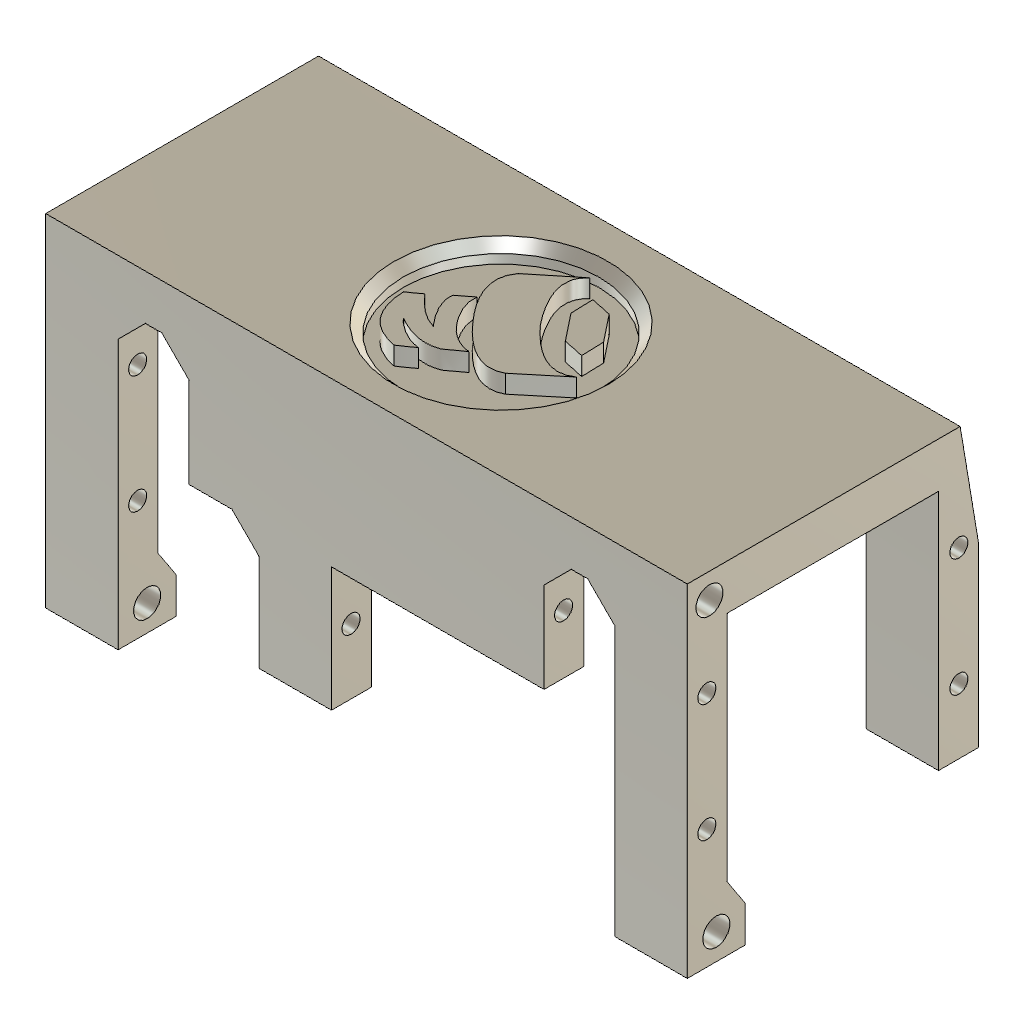
Servo Block native (Autodesk Fusion 360 design; units mm, degrees)
part number: 2026-10-13-22-38-25-267
Autodesk Fusion 360 part; units mm, degrees
(part 1 of 2)
ref_plane "WorkPlane1" through (37.5, 0, 0) normal (1, 0, 0) x (0, 1, 0)
sketch "Plate" plane through (37.5, 0, 0) normal (1, 0, 0) x (0, 0, -1)
  line L0 (-60.7428, -21.1733) -> (-60.7428, 10.9267)
  line L1 (-60.7428, 10.9267) -> (-65.7428, 10.9267)
  line L2 (-65.7428, 10.9267) -> (-65.7428, -21.1733)
  line L3 (-65.7428, -21.1733) -> (-60.7428, -21.1733)
  dimension "d74" = 60.7428
  dimension "d75" = 21.1733
  dimension "d76" = 10.9267
  dimension "d77" = 65.7428
  constraint vertical L0
  constraint horizontal L1
  constraint vertical L2
  constraint horizontal L3
  measures "d74" horizontal distance of origin L0.start
  measures "d75" vertical distance of origin L0.start
  measures "d76" vertical distance of origin L0.end
  measures "d77" horizontal distance of origin L1.end
extrude "Plate (1)" add sketch "Plate" along normal mid plane 70.7696
ref_plane "WorkPlane2" through (0, -18.9733, 0) normal (0, 1, 0) x (0, 0, 1)
sketch "Back wall" plane through (0, -18.9733, 0) normal (0, 1, 0) x (1, 0, 0)
  line L0 (2.1152, -65.7428) -> (2.1152, -28.0592)
  line L1 (2.1152, -28.0592) -> (10.1152, -28.0592)
  line L2 (10.1152, -28.0592) -> (10.1152, -57.7428)
  line L3 (10.1152, -57.7428) -> (13.1152, -60.7428)
  line L4 (13.1152, -60.7428) -> (14.9152, -60.7428)
  line L5 (14.9152, -60.7428) -> (17.9152, -57.7428)
  line L6 (17.9152, -57.7428) -> (17.9152, -47.7592)
  line L7 (17.9152, -47.7592) -> (22.6508, -47.7592)
  line L8 (22.6508, -47.7592) -> (25.6508, -44.7592)
  line L9 (25.6508, -44.7592) -> (25.6508, -34.0592)
  line L10 (25.6508, -34.0592) -> (33.6508, -34.0592)
  line L11 (33.6508, -34.0592) -> (33.6508, -47.7592)
  line L12 (33.6508, -47.7592) -> (57.0848, -47.7592)
  line L13 (57.0848, -47.7592) -> (57.0848, -57.7428)
  line L14 (57.0848, -57.7428) -> (60.0848, -60.7428)
  line L15 (60.0848, -60.7428) -> (61.8848, -60.7428)
  line L16 (61.8848, -60.7428) -> (64.8848, -57.7428)
  line L17 (64.8848, -57.7428) -> (64.8848, -28.0592)
  line L18 (64.8848, -28.0592) -> (72.8848, -28.0592)
  line L19 (72.8848, -28.0592) -> (72.8848, -65.7428)
  line L20 (72.8848, -65.7428) -> (2.1152, -65.7428)
  dimension "d78" = 2.1152
  dimension "d79" = 65.7428
  dimension "d80" = 28.0592
  dimension "d81" = 10.1152
  dimension "d82" = 57.7428
  dimension "d83" = 13.1152
  dimension "d84" = 60.7428
  dimension "d85" = 14.9152
  dimension "d86" = 17.9152
  dimension "d87" = 57.7428
  dimension "d88" = 47.7592
  dimension "d89" = 22.6508
  dimension "d90" = 25.6508
  dimension "d91" = 44.7592
  dimension "d92" = 34.0592
  dimension "d93" = 33.6508
  dimension "d94" = 47.7592
  dimension "d95" = 57.0848
  dimension "d96" = 57.7428
  dimension "d97" = 60.0848
  dimension "d98" = 60.7428
  dimension "d99" = 61.8848
  dimension "d100" = 64.8848
  dimension "d101" = 57.7428
  dimension "d102" = 28.0592
  dimension "d103" = 72.8848
  constraint vertical L0
  constraint horizontal L1
  constraint vertical L2
  constraint horizontal L4
  constraint vertical L6
  constraint horizontal L7
  constraint vertical L9
  constraint horizontal L10
  constraint vertical L11
  constraint horizontal L12
  constraint vertical L13
  constraint horizontal L15
  constraint vertical L17
  constraint horizontal L18
  constraint vertical L19
  constraint horizontal L20
  measures "d78" horizontal distance of origin L0.start
  measures "d79" vertical distance of origin L0.start
  measures "d80" vertical distance of origin L0.end
  measures "d81" horizontal distance of origin L1.end
  measures "d82" vertical distance of origin L2.end
  measures "d83" horizontal distance of origin L3.end
  measures "d84" vertical distance of origin L3.end
  measures "d85" horizontal distance of origin L4.end
  measures "d86" horizontal distance of origin L5.end
  measures "d87" vertical distance of origin L5.end
  measures "d88" vertical distance of origin L6.end
  measures "d89" horizontal distance of origin L7.end
  measures "d90" horizontal distance of origin L8.end
  measures "d91" vertical distance of origin L8.end
  measures "d92" vertical distance of origin L9.end
  measures "d93" horizontal distance of origin L10.end
  measures "d94" vertical distance of origin L11.end
  measures "d95" horizontal distance of origin L12.end
  measures "d96" vertical distance of origin L13.end
  measures "d97" horizontal distance of origin L14.end
  measures "d98" vertical distance of origin L14.end
  measures "d99" horizontal distance of origin L15.end
  measures "d100" horizontal distance of origin L16.end
  measures "d101" vertical distance of origin L16.end
  measures "d102" vertical distance of origin L17.end
  measures "d103" horizontal distance of origin L18.end
extrude "Back wall (1)" add sketch "Back wall" along normal mid plane 4.4
ref_plane "WorkPlane3" through (0, 8.7267, 0) normal (0, 1, 0) x (0, 0, 1)
sketch "Front wall" plane through (0, 8.7267, 0) normal (0, 1, 0) x (1, 0, 0)
  line L0 (2.1152, -65.7428) -> (2.1152, -34.0592)
  line L1 (2.1152, -34.0592) -> (10.1152, -34.0592)
  line L2 (10.1152, -34.0592) -> (10.1152, -57.7428)
  line L3 (10.1152, -57.7428) -> (13.1152, -60.7428)
  line L4 (13.1152, -60.7428) -> (14.9152, -60.7428)
  line L5 (14.9152, -60.7428) -> (17.9152, -57.7428)
  line L6 (17.9152, -57.7428) -> (17.9152, -47.7592)
  line L7 (17.9152, -47.7592) -> (22.6508, -47.7592)
  line L8 (22.6508, -47.7592) -> (25.6508, -44.7592)
  line L9 (25.6508, -44.7592) -> (25.6508, -34.0592)
  line L10 (25.6508, -34.0592) -> (33.6508, -34.0592)
  line L11 (33.6508, -34.0592) -> (33.6508, -57.7428)
  line L12 (33.6508, -57.7428) -> (57.0848, -57.7428)
  line L13 (57.0848, -57.7428) -> (60.0848, -60.7428)
  line L14 (60.0848, -60.7428) -> (61.8848, -60.7428)
  line L15 (61.8848, -60.7428) -> (64.8848, -57.7428)
  line L16 (64.8848, -57.7428) -> (64.8848, -34.0592)
  line L17 (64.8848, -34.0592) -> (72.8848, -34.0592)
  line L18 (72.8848, -34.0592) -> (72.8848, -65.7428)
  line L19 (72.8848, -65.7428) -> (2.1152, -65.7428)
  dimension "d104" = 2.1152
  dimension "d105" = 65.7428
  dimension "d106" = 34.0592
  dimension "d107" = 10.1152
  dimension "d108" = 57.7428
  dimension "d109" = 13.1152
  dimension "d110" = 60.7428
  dimension "d111" = 14.9152
  dimension "d112" = 17.9152
  dimension "d113" = 57.7428
  dimension "d114" = 47.7592
  dimension "d115" = 22.6508
  dimension "d116" = 25.6508
  dimension "d117" = 44.7592
  dimension "d118" = 34.0592
  dimension "d119" = 33.6508
  dimension "d120" = 57.7428
  dimension "d121" = 57.0848
  dimension "d122" = 60.0848
  dimension "d123" = 60.7428
  dimension "d124" = 61.8848
  dimension "d125" = 64.8848
  dimension "d126" = 57.7428
  dimension "d127" = 34.0592
  dimension "d128" = 72.8848
  constraint vertical L0
  constraint horizontal L1
  constraint vertical L2
  constraint horizontal L4
  constraint vertical L6
  constraint horizontal L7
  constraint vertical L9
  constraint horizontal L10
  constraint vertical L11
  constraint horizontal L12
  constraint horizontal L14
  constraint vertical L16
  constraint horizontal L17
  constraint vertical L18
  constraint horizontal L19
  measures "d104" horizontal distance of origin L0.start
  measures "d105" vertical distance of origin L0.start
  measures "d106" vertical distance of origin L0.end
  measures "d107" horizontal distance of origin L1.end
  measures "d108" vertical distance of origin L2.end
  measures "d109" horizontal distance of origin L3.end
  measures "d110" vertical distance of origin L3.end
  measures "d111" horizontal distance of origin L4.end
  measures "d112" horizontal distance of origin L5.end
  measures "d113" vertical distance of origin L5.end
  measures "d114" vertical distance of origin L6.end
  measures "d115" horizontal distance of origin L7.end
  measures "d116" horizontal distance of origin L8.end
  measures "d117" vertical distance of origin L8.end
  measures "d118" vertical distance of origin L9.end
  measures "d119" horizontal distance of origin L10.end
  measures "d120" vertical distance of origin L11.end
  measures "d121" horizontal distance of origin L12.end
  measures "d122" horizontal distance of origin L13.end
  measures "d123" vertical distance of origin L13.end
  measures "d124" horizontal distance of origin L14.end
  measures "d125" horizontal distance of origin L15.end
  measures "d126" vertical distance of origin L15.end
  measures "d127" vertical distance of origin L16.end
  measures "d128" horizontal distance of origin L17.end
extrude "Front wall (1)" add sketch "Front wall" along normal mid plane 4.4
ref_plane "WorkPlane4" through (37.5, 0, 0) normal (1, 0, 0) x (0, 1, 0)
sketch "Front rake" plane through (37.5, 0, 0) normal (1, 0, 0) x (0, 0, -1)
  line L0 (-65.7428, 8.9267) -> (-53.7428, 10.9267)
  line L1 (-53.7428, 10.9267) -> (-53.7428, 11.4267)
  line L2 (-53.7428, 11.4267) -> (-66.2428, 11.4267)
  line L3 (-66.2428, 11.4267) -> (-66.2428, 8.9267)
  line L4 (-66.2428, 8.9267) -> (-65.7428, 8.9267)
  dimension "d129" = 65.7428
  dimension "d130" = 8.9267
  dimension "d131" = 53.7428
  dimension "d132" = 10.9267
  dimension "d133" = 11.4267
  dimension "d134" = 66.2428
  constraint vertical L1
  constraint horizontal L2
  constraint vertical L3
  constraint horizontal L4
  measures "d129" horizontal distance of origin L0.start
  measures "d130" vertical distance of origin L0.start
  measures "d131" horizontal distance of origin L0.end
  measures "d132" vertical distance of origin L0.end
  measures "d133" vertical distance of origin L1.end
  measures "d134" horizontal distance of origin L2.end
extrude "Front rake (1)" cut sketch "Front rake" along normal mid plane 72.7696
ref_plane "WorkPlane5" through (6.1152, 0, 0) normal (1, 0, 0) x (0, 1, 0)
sketch "Foot L" plane through (6.1152, 0, 0) normal (1, 0, 0) x (0, 0, -1)
  line L0 (-28.0592, -17.2733) -> (-28.0592, -14.7733)
  line L1 (-28.0592, -14.7733) -> (-32.0592, -14.7733)
  line L2 (-32.0592, -14.7733) -> (-35.1038, -16.7733)
  line L3 (-35.1038, -16.7733) -> (-35.1038, -17.2733)
  line L4 (-35.1038, -17.2733) -> (-28.0592, -17.2733)
  dimension "d135" = 28.0592
  dimension "d136" = 17.2733
  dimension "d137" = 14.7733
  dimension "d138" = 32.0592
  dimension "d139" = 35.1038
  dimension "d140" = 16.7733
  constraint vertical L0
  constraint horizontal L1
  constraint vertical L3
  constraint horizontal L4
  measures "d135" horizontal distance of origin L0.start
  measures "d136" vertical distance of origin L0.start
  measures "d137" vertical distance of origin L0.end
  measures "d138" horizontal distance of origin L1.end
  measures "d139" horizontal distance of origin L2.end
  measures "d140" vertical distance of origin L2.end
extrude "Foot L (1)" add sketch "Foot L" along normal mid plane 8
ref_plane "WorkPlane6" through (68.8848, 0, 0) normal (1, 0, 0) x (0, 1, 0)
sketch "Foot R" plane through (68.8848, 0, 0) normal (1, 0, 0) x (0, 0, -1)
  line L0 (-28.0592, -17.2733) -> (-28.0592, -14.7733)
  line L1 (-28.0592, -14.7733) -> (-32.0592, -14.7733)
  line L2 (-32.0592, -14.7733) -> (-35.1038, -16.7733)
  line L3 (-35.1038, -16.7733) -> (-35.1038, -17.2733)
  line L4 (-35.1038, -17.2733) -> (-28.0592, -17.2733)
  dimension "d141" = 28.0592
  dimension "d142" = 17.2733
  dimension "d143" = 14.7733
  dimension "d144" = 32.0592
  dimension "d145" = 35.1038
  dimension "d146" = 16.7733
  constraint vertical L0
  constraint horizontal L1
  constraint vertical L3
  constraint horizontal L4
  measures "d141" horizontal distance of origin L0.start
  measures "d142" vertical distance of origin L0.start
  measures "d143" vertical distance of origin L0.end
  measures "d144" horizontal distance of origin L1.end
  measures "d145" horizontal distance of origin L2.end
  measures "d146" vertical distance of origin L2.end
extrude "Foot R (1)" add sketch "Foot R" along normal mid plane 8
ref_plane "WorkPlane7" through (37.5, 0, 0) normal (1, 0, 0) x (0, 1, 0)
sketch "Rod hole back low" plane through (37.5, 0, 0) normal (1, 0, 0) x (0, 0, -1)
  circle A0 centre (-41.2428, -19.0233) radius 1
  dimension "d147" = 2
  dimension "d148" = 41.2428
  dimension "d149" = 19.0233
  measures "d147" diameter of A0
  measures "d148" horizontal distance of origin A0.centre
  measures "d149" vertical distance of origin A0.centre
extrude "Rod hole back low (1)" cut sketch "Rod hole back low" along normal mid plane 71.7696
ref_plane "WorkPlane8" through (37.5, 0, 0) normal (1, 0, 0) x (0, 1, 0)
sketch "Rod hole back high" plane through (37.5, 0, 0) normal (1, 0, 0) x (0, 0, -1)
  circle A0 centre (-54.2428, -19.0233) radius 1
  dimension "d150" = 2
  dimension "d151" = 54.2428
  dimension "d152" = 19.0233
  measures "d150" diameter of A0
  measures "d151" horizontal distance of origin A0.centre
  measures "d152" vertical distance of origin A0.centre
extrude "Rod hole back high (1)" cut sketch "Rod hole back high" along normal mid plane 71.7696
ref_plane "WorkPlane9" through (37.5, 0, 0) normal (1, 0, 0) x (0, 1, 0)
sketch "Rod hole front low" plane through (37.5, 0, 0) normal (1, 0, 0) x (0, 0, -1)
  circle A0 centre (-41.2428, 8.7767) radius 1
  dimension "d153" = 2
  dimension "d154" = 41.2428
  dimension "d155" = 8.7767
  measures "d153" diameter of A0
  measures "d154" horizontal distance of origin A0.centre
  measures "d155" vertical distance of origin A0.centre
extrude "Rod hole front low (1)" cut sketch "Rod hole front low" along normal mid plane 71.7696
ref_plane "WorkPlane10" through (37.5, 0, 0) normal (1, 0, 0) x (0, 1, 0)
sketch "Rod hole front high" plane through (37.5, 0, 0) normal (1, 0, 0) x (0, 0, -1)
  circle A0 centre (-54.2428, 8.7767) radius 1
  dimension "d156" = 2
  dimension "d157" = 54.2428
  dimension "d158" = 8.7767
  measures "d156" diameter of A0
  measures "d157" horizontal distance of origin A0.centre
  measures "d158" vertical distance of origin A0.centre
extrude "Rod hole front high (1)" cut sketch "Rod hole front high" along normal mid plane 71.7696
ref_plane "WorkPlane11" through (6.8652, 0, 0) normal (1, 0, 0) x (0, 1, 0)
sketch "Screw hole top L" plane through (6.8652, 0, 0) normal (1, 0, 0) x (0, 0, -1)
  circle A0 centre (-62.9667, -18.7303) radius 1.5
  dimension "d159" = 3
  dimension "d160" = 62.9667
  dimension "d161" = 18.7303
  measures "d159" diameter of A0
  measures "d160" horizontal distance of origin A0.centre
  measures "d161" vertical distance of origin A0.centre
extrude "Screw hole top L (1)" cut sketch "Screw hole top L" along normal mid plane 10.5
ref_plane "WorkPlane12" through (68.1348, 0, 0) normal (1, 0, 0) x (0, 1, 0)
sketch "Screw hole top R" plane through (68.1348, 0, 0) normal (1, 0, 0) x (0, 0, -1)
  circle A0 centre (-62.9667, -18.7303) radius 1.5
  dimension "d162" = 3
  dimension "d163" = 62.9667
  dimension "d164" = 18.7303
  measures "d162" diameter of A0
  measures "d163" horizontal distance of origin A0.centre
  measures "d164" vertical distance of origin A0.centre
extrude "Screw hole top R (1)" cut sketch "Screw hole top R" along normal mid plane 10.5
ref_plane "WorkPlane13" through (6.1152, 0, 0) normal (1, 0, 0) x (0, 1, 0)
sketch "Screw hole foot L" plane through (6.1152, 0, 0) normal (1, 0, 0) x (0, 0, -1)
  circle A0 centre (-30.943, -17.9733) radius 1.5
  dimension "d165" = 3
  dimension "d166" = 30.943
  dimension "d167" = 17.9733
  measures "d165" diameter of A0
  measures "d166" horizontal distance of origin A0.centre
  measures "d167" vertical distance of origin A0.centre
extrude "Screw hole foot L (1)" cut sketch "Screw hole foot L" along normal mid plane 9
ref_plane "WorkPlane14" through (68.8848, 0, 0) normal (1, 0, 0) x (0, 1, 0)
sketch "Screw hole foot R" plane through (68.8848, 0, 0) normal (1, 0, 0) x (0, 0, -1)
  circle A0 centre (-30.943, -17.9733) radius 1.5
  dimension "d168" = 3
  dimension "d169" = 30.943
  dimension "d170" = 17.9733
  measures "d168" diameter of A0
  measures "d169" horizontal distance of origin A0.centre
  measures "d170" vertical distance of origin A0.centre
extrude "Screw hole foot R (1)" cut sketch "Screw hole foot R" along normal mid plane 9
ref_plane "WorkPlane15" through (0, 0, 64.9928) normal (0, 0, 1) x (1, 0, 0)
sketch "Logo recess" plane through (0, 0, 64.9928) normal (0, 0, 1) x (1, 0, 0)
  circle A0 centre (37.6833, -6.5179) radius 10.7908
  dimension "d171" = 21.5816
  dimension "d172" = 37.6833
  dimension "d173" = 6.5179
  measures "d171" diameter of A0
  measures "d172" horizontal distance of origin A0.centre
  measures "d173" vertical distance of origin A0.centre
extrude "Logo recess (1)" cut sketch "Logo recess" along normal mid plane 2.5
chamfer "Logo rim chamfer" distance 1 angle 45 1 edges at (27.6227, -2.6158, 65.7428) tangent chain off
ref_plane "WorkPlane16" through (0, 0, 64.4928) normal (0, 0, 1) x (1, 0, 0)
sketch "Logo 1" plane through (0, 0, 64.4928) normal (0, 0, 1) x (1, 0, 0)
  line L0 (32.3923, -6.5174) -> (33.8802, -5.3582)
  spline S0 degree 5 poles (33.8802, -5.3582) (33.879, -5.3659) (33.8766, -5.3815) (33.8732, -5.4048) (33.869, -5.4359) (33.8645, -5.4751) (33.8606, -5.5143) (33.8573, -5.5538) (33.8546, -5.5933) (33.8526, -5.6331) (33.8511, -5.6729) (33.8503, -5.7129) (33.8501, -5.753) (33.8504, -5.7933) (33.8514, -5.8336) (33.853, -5.8741) (33.8551, -5.9146) (33.8579, -5.9553) (33.8612, -5.9961) (33.8652, -6.037) (33.8697, -6.078) (33.8748, -6.1191) (33.8804, -6.1603) (33.8866, -6.2016) (33.8934, -6.243) (33.9008, -6.2844) (33.9086, -6.3259) (33.9171, -6.3675) (33.9261, -6.4091) (33.9356, -6.4509) (33.9457, -6.4927) (33.9562, -6.5345) (33.9673, -6.5765) (33.9789, -6.6185) (33.9911, -6.6606) (34.0037, -6.7027) (34.0168, -6.7449) (34.0305, -6.7871) (34.0446, -6.8294) (34.0593, -6.8717) (34.0744, -6.914) (34.09, -6.9564) (34.106, -6.9989) (34.1225, -7.0414) (34.1395, -7.084) (34.1569, -7.1266) (34.1748, -7.1692) (34.1932, -7.2119) (34.212, -7.2546) (34.2313, -7.2973) (34.2509, -7.3401) (34.2711, -7.3829) (34.2916, -7.4257) (34.3125, -7.4686) (34.3339, -7.5115) (34.3557, -7.5544) (34.3779, -7.5974) (34.4006, -7.6405) (34.4236, -7.6836) (34.4471, -7.7266) (34.4709, -7.7697) (34.4951, -7.8127) (34.5197, -7.8558) (34.5446, -7.8988) (34.5699, -7.9419) (34.5956, -7.985) (34.6218, -8.0283) (34.6485, -8.0718) (34.6756, -8.1153) (34.703, -8.1588) (34.7307, -8.2023) (34.7586, -8.2455) (34.7867, -8.2886) (34.815, -8.3314) (34.8435, -8.3741) (34.8725, -8.417) (34.9021, -8.4602) (34.9325, -8.5041) (34.9636, -8.5486) (34.9955, -8.5936) (35.0277, -8.6387) (35.06, -8.6834) (35.0918, -8.7271) (35.1228, -8.7692) (35.1526, -8.8094) (35.1813, -8.8475) (35.2089, -8.8839) (35.2359, -8.919) (35.2626, -8.9533) (35.2895, -8.9874) (35.3168, -9.0217) (35.3445, -9.0561) (35.3726, -9.0907) (35.4009, -9.1252) (35.4293, -9.1594) (35.4577, -9.193) (35.4859, -9.2262) (35.5141, -9.2588) (35.5422, -9.291) (35.5704, -9.3228) (35.5986, -9.3544) (35.627, -9.3857) (35.6556, -9.4169) (35.6844, -9.4478) (35.7132, -9.4785) (35.7422, -9.5088) (35.7711, -9.5388) (35.7998, -9.5683) (35.8284, -9.5973) (35.8569, -9.6258) (35.8854, -9.6539) (35.9141, -9.6819) (35.9432, -9.7098) (35.9729, -9.7379) (36.0031, -9.7659) (36.0332, -9.7936) (36.0628, -9.8205) (36.0914, -9.8463) (36.1187, -9.8707) (36.1453, -9.8943) (36.1723, -9.9177) (36.201, -9.9423) (36.233, -9.9689) (36.269, -9.9985) (36.3094, -10.031) (36.3536, -10.066) (36.4005, -10.1025) (36.4488, -10.1395) (36.4973, -10.1759) (36.545, -10.2108) (36.5913, -10.2439) (36.6362, -10.275) (36.6802, -10.3045) (36.7235, -10.3328) (36.7669, -10.3604) (36.8107, -10.3877) (36.855, -10.4147) (36.8998, -10.4415) (36.945, -10.4679) (36.9902, -10.4937) (37.0353, -10.5187) (37.0801, -10.5429) (37.1245, -10.5661) (37.1686, -10.5885) (37.2125, -10.6101) (37.2563, -10.631) (37.3, -10.6513) (37.3437, -10.671) (37.3873, -10.6901) (37.4308, -10.7086) (37.4741, -10.7265) (37.5171, -10.7437) (37.5599, -10.7603) (37.6025, -10.7761) (37.6447, -10.7914) (37.6867, -10.806) (37.7284, -10.82) (37.7699, -10.8335) (37.8111, -10.8464) (37.8519, -10.8587) (37.8925, -10.8705) (37.9327, -10.8817) (37.9725, -10.8924) (38.0119, -10.9025) (38.0509, -10.9122) (38.0894, -10.9213) (38.1275, -10.93) (38.1652, -10.9382) (38.2023, -10.946) (38.239, -10.9533) (38.2751, -10.9603) (38.3106, -10.9668) (38.3456, -10.973) (38.3799, -10.9788) (38.4136, -10.9842) (38.4466, -10.9894) (38.4789, -10.9943) (38.5105, -10.999) (38.5412, -11.0034) (38.5711, -11.0077) (38.6001, -11.0119) (38.6225, -11.0151) (38.639, -11.0174) (38.6498, -11.0189) (38.6551, -11.0197) knots 0 0 0 0 0 0 0.00555556 0.01111111 0.01666667 0.02222222 0.02777778 0.03333333 0.03888889 0.04444444 0.05 0.05555556 0.06111111 0.06666667 0.07222222 0.07777778 0.08333333 0.08888889 0.09444444 0.1 0.10555556 0.11111111 0.11666667 0.12222222 0.12777778 0.13333333 0.13888889 0.14444444 0.15 0.15555556 0.16111111 0.16666667 0.17222222 0.17777778 0.18333333 0.18888889 0.19444444 0.2 0.20555556 0.21111111 0.21666667 0.22222222 0.22777778 0.23333333 0.23888889 0.24444444 0.25 0.25555556 0.26111111 0.26666667 0.27222222 0.27777778 0.28333333 0.28888889 0.29444444 0.3 0.30555556 0.31111111 0.31666667 0.32222222 0.32777778 0.33333333 0.33888889 0.34444444 0.35 0.35555556 0.36111111 0.36666667 0.37222222 0.37777778 0.38333333 0.38888889 0.39444444 0.4 0.40555556 0.41111111 0.41666667 0.42222222 0.42777778 0.43333333 0.43888889 0.44444444 0.45 0.45555556 0.46111111 0.46666667 0.47222222 0.47777778 0.48333333 0.48888889 0.49444444 0.5 0.50555556 0.51111111 0.51666667 0.52222222 0.52777778 0.53333333 0.53888889 0.54444444 0.55 0.55555556 0.56111111 0.56666667 0.57222222 0.57777778 0.58333333 0.58888889 0.59444444 0.6 0.60555556 0.61111111 0.61666667 0.62222222 0.62777778 0.63333333 0.63888889 0.64444444 0.65 0.65555556 0.66111111 0.66666667 0.67222222 0.67777778 0.68333333 0.68888889 0.69444444 0.7 0.70555556 0.71111111 0.71666667 0.72222222 0.72777778 0.73333333 0.73888889 0.74444444 0.75 0.75555556 0.76111111 0.76666667 0.77222222 0.77777778 0.78333333 0.78888889 0.79444444 0.8 0.80555556 0.81111111 0.81666667 0.82222222 0.82777778 0.83333333 0.83888889 0.84444444 0.85 0.85555556 0.86111111 0.86666667 0.87222222 0.87777778 0.88333333 0.88888889 0.89444444 0.9 0.90555556 0.91111111 0.91666667 0.92222222 0.92777778 0.93333333 0.93888889 0.94444444 0.95 0.95555556 0.96111111 0.96666667 0.97222222 0.97777778 0.98333333 0.98888889 0.99444444 1 1 1 1 1 1
  spline S1 degree 5 poles (38.6551, -11.0197) (38.6411, -11.0298) (38.613, -11.05) (38.5707, -11.0807) (38.5138, -11.1222) (38.4421, -11.1751) (38.3696, -11.2289) (38.2966, -11.2835) (38.2231, -11.3386) (38.1494, -11.3939) (38.0757, -11.4489) (38.0023, -11.5031) (37.9293, -11.5563) (37.8568, -11.6084) (37.7846, -11.6595) (37.7125, -11.7104) (37.6397, -11.7622) (37.5656, -11.816) (37.4898, -11.8727) (37.4122, -11.9325) (37.333, -11.9949) (37.2531, -12.0583) (37.174, -12.12) (37.0972, -12.1773) (37.0241, -12.2277) (36.9556, -12.2695) (36.8918, -12.3021) (36.832, -12.3267) (36.7746, -12.3459) (36.7179, -12.3623) (36.6604, -12.3785) (36.6012, -12.3959) (36.5404, -12.4146) (36.4784, -12.4337) (36.4159, -12.4523) (36.3534, -12.4692) (36.2912, -12.4842) (36.2293, -12.4973) (36.1673, -12.5089) (36.1051, -12.5196) (36.0424, -12.5296) (35.9793, -12.5391) (35.9156, -12.5478) (35.8517, -12.5557) (35.7876, -12.5625) (35.7234, -12.5681) (35.6591, -12.5726) (35.5946, -12.576) (35.5299, -12.5784) (35.465, -12.5798) (35.3999, -12.5804) (35.3345, -12.58) (35.2689, -12.5788) (35.2031, -12.5765) (35.1372, -12.5734) (35.0712, -12.5692) (35.005, -12.5641) (34.9386, -12.558) (34.8721, -12.551) (34.8055, -12.5431) (34.7387, -12.5342) (34.6718, -12.5245) (34.6047, -12.5138) (34.5375, -12.5023) (34.4703, -12.4899) (34.4029, -12.4767) (34.3353, -12.4625) (34.2677, -12.4475) (34.2, -12.4316) (34.1322, -12.4148) (34.0642, -12.3972) (33.9962, -12.3788) (33.9281, -12.3595) (33.8599, -12.3394) (33.7916, -12.3185) (33.7233, -12.2968) (33.6549, -12.2743) (33.5864, -12.251) (33.5178, -12.2269) (33.4492, -12.202) (33.3805, -12.1764) (33.3117, -12.15) (33.2429, -12.1228) (33.174, -12.0948) (33.1051, -12.0662) (33.0361, -12.0367) (32.9671, -12.0066) (32.898, -11.9758) (32.8289, -11.9442) (32.7597, -11.9119) (32.6904, -11.8789) (32.6212, -11.8452) (32.5518, -11.8109) (32.4825, -11.7758) (32.4131, -11.7401) (32.3436, -11.7037) (32.2742, -11.6666) (32.2047, -11.6289) (32.1351, -11.5905) (32.0655, -11.5515) (31.9959, -11.5118) (31.9402, -11.4796) (31.8984, -11.4551) (31.8705, -11.4387) (31.8566, -11.4304) knots 0 0 0 0 0 0 0.01 0.02 0.03 0.04 0.05 0.06 0.07 0.08 0.09 0.1 0.11 0.12 0.13 0.14 0.15 0.16 0.17 0.18 0.19 0.2 0.21 0.22 0.23 0.24 0.25 0.26 0.27 0.28 0.29 0.3 0.31 0.32 0.33 0.34 0.35 0.36 0.37 0.38 0.39 0.4 0.41 0.42 0.43 0.44 0.45 0.46 0.47 0.48 0.49 0.5 0.51 0.52 0.53 0.54 0.55 0.56 0.57 0.58 0.59 0.6 0.61 0.62 0.63 0.64 0.65 0.66 0.67 0.68 0.69 0.7 0.71 0.72 0.73 0.74 0.75 0.76 0.77 0.78 0.79 0.8 0.81 0.82 0.83 0.84 0.85 0.86 0.87 0.88 0.89 0.9 0.91 0.92 0.93 0.94 0.95 0.96 0.97 0.98 0.99 1 1 1 1 1 1
  spline S2 degree 5 poles (31.8566, -11.4304) (31.8588, -11.4336) (31.8632, -11.4398) (31.8694, -11.4488) (31.877, -11.4598) (31.8858, -11.4722) (31.8941, -11.4839) (31.903, -11.4958) (31.9139, -11.5098) (31.928, -11.5272) (31.9463, -11.5489) (31.9685, -11.5748) (31.9939, -11.6036) (32.0212, -11.634) (32.0495, -11.6646) (32.078, -11.6944) (32.1065, -11.7234) (32.1354, -11.7519) (32.1651, -11.7805) (32.1959, -11.8097) (32.2279, -11.8396) (32.2611, -11.8702) (32.2954, -11.9012) (32.3305, -11.9326) (32.3663, -11.9639) (32.4025, -11.9951) (32.4394, -12.0262) (32.4769, -12.0573) (32.515, -12.0884) (32.5538, -12.1196) (32.5933, -12.151) (32.6335, -12.1824) (32.6743, -12.2139) (32.7158, -12.2453) (32.7577, -12.2767) (32.8002, -12.3079) (32.8431, -12.3391) (32.8866, -12.3701) (32.9306, -12.4009) (32.975, -12.4317) (33.02, -12.4623) (33.0655, -12.4927) (33.1114, -12.523) (33.1577, -12.5531) (33.2045, -12.5829) (33.2517, -12.6125) (33.2993, -12.6418) (33.3473, -12.6709) (33.3957, -12.6996) (33.4445, -12.7281) (33.4937, -12.7562) (33.5432, -12.7841) (33.593, -12.8116) (33.6433, -12.8387) (33.6938, -12.8655) (33.7447, -12.8918) (33.7959, -12.9177) (33.8474, -12.9432) (33.8992, -12.9683) (33.9513, -12.9928) (34.0037, -13.0169) (34.0563, -13.0405) (34.1092, -13.0635) (34.1623, -13.086) (34.2157, -13.108) (34.2694, -13.1294) (34.3232, -13.1502) (34.3773, -13.1704) (34.4316, -13.19) (34.4861, -13.209) (34.5407, -13.2273) (34.5956, -13.2448) (34.6506, -13.2617) (34.7058, -13.2778) (34.7612, -13.2932) (34.8167, -13.3078) (34.8723, -13.3216) (34.928, -13.3347) (34.9839, -13.3469) (35.0398, -13.3582) (35.0959, -13.3687) (35.1519, -13.3782) (35.2081, -13.3868) (35.2642, -13.3944) (35.3204, -13.4011) (35.3767, -13.4068) (35.4217, -13.4105) (35.4554, -13.4129) (35.4779, -13.4143) (35.4892, -13.4149) knots 0 0 0 0 0 0 0.01176471 0.02352941 0.03529412 0.04705882 0.05882353 0.07058824 0.08235294 0.09411765 0.10588235 0.11764706 0.12941176 0.14117647 0.15294118 0.16470588 0.17647059 0.18823529 0.2 0.21176471 0.22352941 0.23529412 0.24705882 0.25882353 0.27058824 0.28235294 0.29411765 0.30588235 0.31764706 0.32941176 0.34117647 0.35294118 0.36470588 0.37647059 0.38823529 0.4 0.41176471 0.42352941 0.43529412 0.44705882 0.45882353 0.47058824 0.48235294 0.49411765 0.50588235 0.51764706 0.52941176 0.54117647 0.55294118 0.56470588 0.57647059 0.58823529 0.6 0.61176471 0.62352941 0.63529412 0.64705882 0.65882353 0.67058824 0.68235294 0.69411765 0.70588235 0.71764706 0.72941176 0.74117647 0.75294118 0.76470588 0.77647059 0.78823529 0.8 0.81176471 0.82352941 0.83529412 0.84705882 0.85882353 0.87058824 0.88235294 0.89411765 0.90588235 0.91764706 0.92941176 0.94117647 0.95294118 0.96470588 0.97647059 0.98823529 1 1 1 1 1 1
  spline S3 degree 5 poles (35.4892, -13.4149) (35.4804, -13.4214) (35.4629, -13.4343) (35.4366, -13.4537) (35.4017, -13.4793) (35.3583, -13.5112) (35.315, -13.5429) (35.2719, -13.5744) (35.2291, -13.6056) (35.1864, -13.6366) (35.1438, -13.6675) (35.1015, -13.6981) (35.0594, -13.7285) (35.0175, -13.7587) (34.9757, -13.7886) (34.9342, -13.8184) (34.8929, -13.8479) (34.8517, -13.8772) (34.8108, -13.9063) (34.7701, -13.9352) (34.7296, -13.9638) (34.6893, -13.9922) (34.6491, -14.0204) (34.6092, -14.0484) (34.5695, -14.0762) (34.5299, -14.1037) (34.4906, -14.131) (34.4515, -14.1581) (34.4126, -14.1849) (34.3739, -14.2115) (34.3354, -14.2378) (34.2972, -14.2639) (34.2592, -14.2898) (34.2213, -14.3154) (34.1837, -14.3408) (34.1464, -14.366) (34.1092, -14.3909) (34.0722, -14.4156) (34.0355, -14.44) (33.999, -14.4642) (33.9627, -14.4882) (33.9338, -14.5071) (33.9123, -14.5212) (33.898, -14.5305) (33.8908, -14.5352) knots 0 0 0 0 0 0 0.025 0.05 0.075 0.1 0.125 0.15 0.175 0.2 0.225 0.25 0.275 0.3 0.325 0.35 0.375 0.4 0.425 0.45 0.475 0.5 0.525 0.55 0.575 0.6 0.625 0.65 0.675 0.7 0.725 0.75 0.775 0.8 0.825 0.85 0.875 0.9 0.925 0.95 0.975 1 1 1 1 1 1
  spline S4 degree 5 poles (33.8908, -14.5352) (33.8804, -14.5332) (33.8595, -14.5291) (33.8283, -14.5229) (33.7868, -14.5144) (33.7351, -14.5035) (33.6837, -14.4924) (33.6324, -14.4809) (33.5814, -14.4691) (33.5306, -14.457) (33.48, -14.4446) (33.4296, -14.4319) (33.3794, -14.4189) (33.3295, -14.4056) (33.2797, -14.392) (33.2302, -14.378) (33.181, -14.3637) (33.1319, -14.3492) (33.0831, -14.3342) (33.0346, -14.319) (32.9863, -14.3034) (32.9382, -14.2875) (32.8903, -14.2713) (32.8427, -14.2548) (32.7954, -14.238) (32.7482, -14.2208) (32.7014, -14.2034) (32.6547, -14.1856) (32.6084, -14.1674) (32.5622, -14.1489) (32.5164, -14.1301) (32.4708, -14.1109) (32.4254, -14.0914) (32.3804, -14.0716) (32.3356, -14.0514) (32.2911, -14.0309) (32.2468, -14.0101) (32.2028, -13.9889) (32.1591, -13.9674) (32.1157, -13.9455) (32.0726, -13.9233) (32.0297, -13.9008) (31.9871, -13.8779) (31.9448, -13.8547) (31.9028, -13.8311) (31.8611, -13.8072) (31.8197, -13.783) (31.7786, -13.7584) (31.7378, -13.7334) (31.6972, -13.7081) (31.657, -13.6825) (31.6171, -13.6565) (31.5775, -13.6302) (31.5382, -13.6035) (31.4993, -13.5765) (31.4606, -13.5492) (31.4222, -13.5215) (31.3842, -13.4934) (31.3465, -13.465) (31.3091, -13.4363) (31.2721, -13.4072) (31.2353, -13.3778) (31.1989, -13.348) (31.1629, -13.3179) (31.1271, -13.2875) (31.0917, -13.2567) (31.0567, -13.2256) (31.0219, -13.1941) (30.9876, -13.1623) (30.9535, -13.1301) (30.9198, -13.0977) (30.8865, -13.0649) (30.8535, -13.0317) (30.8208, -12.9982) (30.7885, -12.9644) (30.7565, -12.9303) (30.7249, -12.8958) (30.6936, -12.861) (30.6627, -12.8259) (30.6322, -12.7905) (30.602, -12.7547) (30.5722, -12.7187) (30.5427, -12.6823) (30.5136, -12.6455) (30.4848, -12.6085) (30.4564, -12.5711) (30.4284, -12.5335) (30.4008, -12.4955) (30.3735, -12.4572) (30.3465, -12.4186) (30.32, -12.3798) (30.2937, -12.3406) (30.2679, -12.3011) (30.2424, -12.2613) (30.2173, -12.2212) (30.1925, -12.1808) (30.1681, -12.1402) (30.1441, -12.0992) (30.1205, -12.058) (30.0972, -12.0164) (30.0743, -11.9746) (30.0517, -11.9325) (30.0295, -11.8902) (30.0077, -11.8476) (29.9862, -11.8047) (29.965, -11.7615) (29.9443, -11.718) (29.9239, -11.6743) (29.9039, -11.6303) (29.8842, -11.586) (29.8649, -11.5415) (29.846, -11.4967) (29.8274, -11.4517) (29.8092, -11.4064) (29.7913, -11.3609) (29.7738, -11.3151) (29.7567, -11.2691) (29.7398, -11.2229) (29.7234, -11.1764) (29.7073, -11.1296) (29.6915, -11.0826) (29.6761, -11.0354) (29.6611, -10.9879) (29.6464, -10.9402) (29.632, -10.8923) (29.618, -10.8442) (29.6043, -10.7958) (29.5909, -10.7472) (29.5779, -10.6984) (29.5652, -10.6494) (29.5529, -10.6001) (29.5409, -10.5507) (29.5293, -10.501) (29.518, -10.4511) (29.507, -10.401) (29.4964, -10.3508) (29.486, -10.3003) (29.476, -10.2496) (29.4664, -10.1986) (29.457, -10.1475) (29.448, -10.0962) (29.4393, -10.0447) (29.4309, -9.993) (29.4228, -9.9411) (29.4151, -9.8891) (29.4076, -9.8368) (29.4005, -9.7843) (29.3937, -9.7317) (29.3871, -9.6789) (29.3809, -9.6259) (29.375, -9.5727) (29.3694, -9.5193) (29.3642, -9.4658) (29.3592, -9.4121) (29.3545, -9.3582) (29.3501, -9.3042) (29.3461, -9.2499) (29.3423, -9.1955) (29.3388, -9.141) (29.3356, -9.0862) (29.3327, -9.0313) (29.3306, -8.9873) (29.3292, -8.9542) (29.3282, -8.9321) (29.3278, -8.921) knots 0 0 0 0 0 0 0.00625 0.0125 0.01875 0.025 0.03125 0.0375 0.04375 0.05 0.05625 0.0625 0.06875 0.075 0.08125 0.0875 0.09375 0.1 0.10625 0.1125 0.11875 0.125 0.13125 0.1375 0.14375 0.15 0.15625 0.1625 0.16875 0.175 0.18125 0.1875 0.19375 0.2 0.20625 0.2125 0.21875 0.225 0.23125 0.2375 0.24375 0.25 0.25625 0.2625 0.26875 0.275 0.28125 0.2875 0.29375 0.3 0.30625 0.3125 0.31875 0.325 0.33125 0.3375 0.34375 0.35 0.35625 0.3625 0.36875 0.375 0.38125 0.3875 0.39375 0.4 0.40625 0.4125 0.41875 0.425 0.43125 0.4375 0.44375 0.45 0.45625 0.4625 0.46875 0.475 0.48125 0.4875 0.49375 0.5 0.50625 0.5125 0.51875 0.525 0.53125 0.5375 0.54375 0.55 0.55625 0.5625 0.56875 0.575 0.58125 0.5875 0.59375 0.6 0.60625 0.6125 0.61875 0.625 0.63125 0.6375 0.64375 0.65 0.65625 0.6625 0.66875 0.675 0.68125 0.6875 0.69375 0.7 0.70625 0.7125 0.71875 0.725 0.73125 0.7375 0.74375 0.75 0.75625 0.7625 0.76875 0.775 0.78125 0.7875 0.79375 0.8 0.80625 0.8125 0.81875 0.825 0.83125 0.8375 0.84375 0.85 0.85625 0.8625 0.86875 0.875 0.88125 0.8875 0.89375 0.9 0.90625 0.9125 0.91875 0.925 0.93125 0.9375 0.94375 0.95 0.95625 0.9625 0.96875 0.975 0.98125 0.9875 0.99375 1 1 1 1 1 1
  spline S5 degree 5 poles (29.3278, -8.921) (29.3336, -8.9172) (29.3453, -8.9096) (29.3628, -8.8981) (29.3864, -8.8826) (29.4161, -8.8629) (29.4462, -8.8429) (29.4765, -8.8226) (29.5071, -8.8021) (29.538, -8.7812) (29.5691, -8.7599) (29.6005, -8.7384) (29.6322, -8.7166) (29.6642, -8.6945) (29.6964, -8.6722) (29.7289, -8.6495) (29.7617, -8.6265) (29.7947, -8.6032) (29.8279, -8.5797) (29.8614, -8.5559) (29.8952, -8.5318) (29.9292, -8.5074) (29.9635, -8.4827) (29.998, -8.4578) (30.0328, -8.4325) (30.0678, -8.407) (30.1031, -8.3813) (30.1386, -8.3553) (30.1743, -8.329) (30.2103, -8.3025) (30.2466, -8.2757) (30.2831, -8.2486) (30.3198, -8.2213) (30.3568, -8.1937) (30.394, -8.1659) (30.4314, -8.1378) (30.469, -8.1094) (30.5069, -8.0808) (30.545, -8.052) (30.5834, -8.0228) (30.6219, -7.9935) (30.6529, -7.9698) (30.6763, -7.952) (30.6919, -7.94) (30.6997, -7.934) knots 0 0 0 0 0 0 0.025 0.05 0.075 0.1 0.125 0.15 0.175 0.2 0.225 0.25 0.275 0.3 0.325 0.35 0.375 0.4 0.425 0.45 0.475 0.5 0.525 0.55 0.575 0.6 0.625 0.65 0.675 0.7 0.725 0.75 0.775 0.8 0.825 0.85 0.875 0.9 0.925 0.95 0.975 1 1 1 1 1 1
  spline S6 degree 5 poles (30.6997, -7.934) (30.7085, -7.9441) (30.726, -7.9642) (30.7523, -7.9942) (30.7874, -8.0341) (30.8313, -8.0836) (30.8752, -8.1327) (30.9191, -8.1814) (30.963, -8.2298) (31.0069, -8.2778) (31.0509, -8.3255) (31.0949, -8.3727) (31.1389, -8.4196) (31.1829, -8.4661) (31.227, -8.5122) (31.271, -8.5579) (31.3151, -8.6033) (31.3592, -8.6482) (31.4034, -8.6928) (31.4475, -8.737) (31.4916, -8.7808) (31.5358, -8.8242) (31.58, -8.8672) (31.6242, -8.9097) (31.6684, -8.9519) (31.7126, -8.9936) (31.7569, -9.0349) (31.8012, -9.0758) (31.8455, -9.1163) (31.8898, -9.1563) (31.9342, -9.1959) (31.9785, -9.2351) (32.0229, -9.2739) (32.0673, -9.3122) (32.1117, -9.35) (32.1561, -9.3875) (32.2006, -9.4244) (32.245, -9.4609) (32.2895, -9.497) (32.334, -9.5326) (32.3785, -9.5677) (32.4231, -9.6024) (32.4676, -9.6366) (32.5122, -9.6703) (32.5567, -9.7035) (32.6013, -9.7362) (32.6459, -9.7685) (32.6906, -9.8002) (32.7352, -9.8315) (32.7798, -9.8623) (32.8245, -9.8925) (32.8691, -9.9223) (32.9138, -9.9516) (32.9585, -9.9803) (33.0032, -10.0085) (33.048, -10.0361) (33.0927, -10.0633) (33.1374, -10.0899) (33.1822, -10.1159) (33.227, -10.1414) (33.2717, -10.1664) (33.3164, -10.1908) (33.3612, -10.2147) (33.4059, -10.238) (33.4507, -10.2607) (33.4955, -10.2828) (33.5402, -10.3044) (33.585, -10.3254) (33.6298, -10.3458) (33.6745, -10.3656) (33.7193, -10.3848) (33.764, -10.4034) (33.8088, -10.4215) (33.8535, -10.4389) (33.8982, -10.4556) (33.9429, -10.4718) (33.9876, -10.4873) (34.0322, -10.5022) (34.0768, -10.5165) (34.1214, -10.5301) (34.166, -10.5431) (34.2017, -10.553) (34.2284, -10.5601) (34.2462, -10.5647) (34.2551, -10.567) knots 0 0 0 0 0 0 0.0125 0.025 0.0375 0.05 0.0625 0.075 0.0875 0.1 0.1125 0.125 0.1375 0.15 0.1625 0.175 0.1875 0.2 0.2125 0.225 0.2375 0.25 0.2625 0.275 0.2875 0.3 0.3125 0.325 0.3375 0.35 0.3625 0.375 0.3875 0.4 0.4125 0.425 0.4375 0.45 0.4625 0.475 0.4875 0.5 0.5125 0.525 0.5375 0.55 0.5625 0.575 0.5875 0.6 0.6125 0.625 0.6375 0.65 0.6625 0.675 0.6875 0.7 0.7125 0.725 0.7375 0.75 0.7625 0.775 0.7875 0.8 0.8125 0.825 0.8375 0.85 0.8625 0.875 0.8875 0.9 0.9125 0.925 0.9375 0.95 0.9625 0.975 0.9875 1 1 1 1 1 1
  spline S7 degree 5 poles (34.2551, -10.567) (34.2457, -10.556) (34.2269, -10.534) (34.1988, -10.5011) (34.1616, -10.4572) (34.1156, -10.4024) (34.0701, -10.3476) (34.0251, -10.293) (33.9805, -10.2385) (33.9364, -10.184) (33.8928, -10.1296) (33.8496, -10.0753) (33.807, -10.021) (33.7648, -9.9669) (33.7231, -9.9128) (33.6819, -9.8588) (33.6412, -9.8049) (33.601, -9.751) (33.5613, -9.6973) (33.5222, -9.6436) (33.4836, -9.5901) (33.4455, -9.5366) (33.4079, -9.4832) (33.3709, -9.4299) (33.3344, -9.3767) (33.2985, -9.3235) (33.2631, -9.2705) (33.2283, -9.2176) (33.194, -9.1647) (33.1604, -9.112) (33.1273, -9.0593) (33.0947, -9.0068) (33.0628, -8.9543) (33.0315, -8.902) (33.0008, -8.8497) (32.9707, -8.7976) (32.9413, -8.7456) (32.9124, -8.6936) (32.8842, -8.6418) (32.8566, -8.5901) (32.8297, -8.5385) (32.8034, -8.487) (32.7777, -8.4357) (32.7528, -8.3844) (32.7285, -8.3333) (32.7049, -8.2823) (32.6821, -8.2314) (32.6599, -8.1807) (32.6384, -8.1301) (32.6177, -8.0796) (32.5976, -8.0293) (32.5783, -7.9791) (32.5597, -7.929) (32.5419, -7.8791) (32.5248, -7.8294) (32.5085, -7.7798) (32.493, -7.7304) (32.4783, -7.6811) (32.4644, -7.6319) (32.4513, -7.583) (32.439, -7.5342) (32.4276, -7.4857) (32.4169, -7.4373) (32.4071, -7.3891) (32.3982, -7.341) (32.3901, -7.2932) (32.3829, -7.2456) (32.3765, -7.1982) (32.3711, -7.151) (32.3665, -7.1041) (32.3629, -7.0573) (32.3601, -7.0109) (32.3583, -6.9646) (32.3574, -6.9186) (32.3574, -6.8729) (32.3584, -6.8275) (32.3603, -6.7823) (32.3632, -6.7374) (32.367, -6.6928) (32.3718, -6.6485) (32.3776, -6.6045) (32.383, -6.5695) (32.3875, -6.5434) (32.3907, -6.5261) (32.3923, -6.5174) knots 0 0 0 0 0 0 0.0125 0.025 0.0375 0.05 0.0625 0.075 0.0875 0.1 0.1125 0.125 0.1375 0.15 0.1625 0.175 0.1875 0.2 0.2125 0.225 0.2375 0.25 0.2625 0.275 0.2875 0.3 0.3125 0.325 0.3375 0.35 0.3625 0.375 0.3875 0.4 0.4125 0.425 0.4375 0.45 0.4625 0.475 0.4875 0.5 0.5125 0.525 0.5375 0.55 0.5625 0.575 0.5875 0.6 0.6125 0.625 0.6375 0.65 0.6625 0.675 0.6875 0.7 0.7125 0.725 0.7375 0.75 0.7625 0.775 0.7875 0.8 0.8125 0.825 0.8375 0.85 0.8625 0.875 0.8875 0.9 0.9125 0.925 0.9375 0.95 0.9625 0.975 0.9875 1 1 1 1 1 1
  point P0 (33.8585, -5.54)
  point P1 (33.8503, -5.7263)
  point P2 (33.8554, -5.9169)
  point P3 (33.874, -6.112)
  point P4 (33.906, -6.3116)
  point P5 (33.9515, -6.5155)
  point P6 (34.0104, -6.724)
  point P7 (34.0828, -6.9368)
  point P8 (34.1685, -7.1541)
  point P9 (34.2678, -7.3758)
  point P10 (34.3804, -7.602)
  point P11 (34.5065, -7.8326)
  point P12 (34.646, -8.0676)
  point P13 (34.799, -8.3071)
  point P14 (34.9654, -8.551)
  point P15 (35.1452, -8.7993)
  point P16 (35.2851, -8.9818)
  point P17 (35.4247, -9.1537)
  point P18 (35.5638, -9.3153)
  point P19 (35.7024, -9.4669)
  point P20 (35.8402, -9.609)
  point P21 (35.9771, -9.7417)
  point P22 (36.1129, -9.8655)
  point P23 (36.2474, -9.9807)
  point P24 (36.5119, -10.1865)
  point P25 (36.7693, -10.3618)
  point P26 (37.0183, -10.5092)
  point P27 (37.2575, -10.6314)
  point P28 (37.4855, -10.731)
  point P29 (37.7009, -10.8107)
  point P30 (37.9025, -10.8732)
  point P31 (38.0889, -10.9211)
  point P32 (38.2587, -10.9571)
  point P33 (38.4106, -10.9837)
  point P34 (38.5432, -11.0037)
  point P35 (38.2478, -11.3201)
  point P36 (37.8284, -11.6284)
  point P37 (37.397, -11.9447)
  point P38 (36.9536, -12.269)
  point P39 (36.6825, -12.3723)
  point P40 (36.4051, -12.4549)
  point P41 (36.1213, -12.5167)
  point P42 (35.8312, -12.5577)
  point P43 (35.5348, -12.578)
  point P44 (35.2321, -12.5774)
  point P45 (34.923, -12.5562)
  point P46 (34.6076, -12.5141)
  point P47 (34.2859, -12.4514)
  point P48 (33.9578, -12.3678)
  point P49 (33.6234, -12.2635)
  point P50 (33.2827, -12.1384)
  point P51 (32.9357, -11.9925)
  point P52 (32.5823, -11.8259)
  point P53 (32.2226, -11.6385)
  point P54 (31.8904, -11.4786)
  point P55 (31.9321, -11.5319)
  point P56 (32.0378, -11.6518)
  point P57 (32.1717, -11.7867)
  point P58 (32.3315, -11.9333)
  point P59 (32.5151, -12.0884)
  point P60 (32.7204, -12.2487)
  point P61 (32.9451, -12.4109)
  point P62 (33.1872, -12.5718)
  point P63 (33.4444, -12.7279)
  point P64 (33.7147, -12.8762)
  point P65 (33.9959, -13.0132)
  point P66 (34.2857, -13.1356)
  point P67 (34.5821, -13.2404)
  point P68 (34.883, -13.324)
  point P69 (35.1861, -13.3833)
  point P70 (35.265, -13.5794)
  point P71 (35.0477, -13.7369)
  point P72 (34.8374, -13.8874)
  point P73 (34.6342, -14.0309)
  point P74 (34.4378, -14.1675)
  point P75 (34.2485, -14.297)
  point P76 (34.0662, -14.4196)
  point P77 (33.6215, -14.4783)
  point P78 (33.3604, -14.4138)
  point P79 (33.1074, -14.3416)
  point P80 (32.8627, -14.2617)
  point P81 (32.6261, -14.1743)
  point P82 (32.3976, -14.0791)
  point P83 (32.1774, -13.9763)
  point P84 (31.9653, -13.8659)
  point P85 (31.7614, -13.7478)
  point P86 (31.5657, -13.6221)
  point P87 (31.3781, -13.4887)
  point P88 (31.1987, -13.3477)
  point P89 (31.0275, -13.199)
  point P90 (30.8645, -13.0427)
  point P91 (30.7096, -12.8787)
  point P92 (30.5629, -12.7071)
  point P93 (30.4244, -12.5278)
  point P94 (30.2941, -12.3409)
  point P95 (30.1719, -12.1463)
  point P96 (30.058, -11.9441)
  point P97 (29.9521, -11.7343)
  point P98 (29.8545, -11.5167)
  point P99 (29.7651, -11.2916)
  point P100 (29.6838, -11.0588)
  point P101 (29.6107, -10.8183)
  point P102 (29.5457, -10.5702)
  point P103 (29.489, -10.3145)
  point P104 (29.4404, -10.0511)
  point P105 (29.4, -9.78)
  point P106 (29.3677, -9.5013)
  point P107 (29.3437, -9.215)
  point P108 (29.4701, -8.8269)
  point P109 (29.6208, -8.7245)
  point P110 (29.7798, -8.6137)
  point P111 (29.9471, -8.4945)
  point P112 (30.1227, -8.3669)
  point P113 (30.3067, -8.231)
  point P114 (30.4991, -8.0867)
  point P115 (30.9398, -8.2042)
  point P116 (31.1775, -8.4603)
  point P117 (31.4129, -8.7023)
  point P118 (31.6458, -8.9303)
  point P119 (31.8764, -9.1441)
  point P120 (32.1046, -9.3439)
  point P121 (32.3304, -9.5296)
  point P122 (32.5538, -9.7012)
  point P123 (32.7748, -9.8587)
  point P124 (32.9934, -10.0022)
  point P125 (33.2097, -10.1315)
  point P126 (33.4235, -10.2468)
  point P127 (33.635, -10.348)
  point P128 (33.8441, -10.4351)
  point P129 (34.0508, -10.5081)
  point P130 (33.9953, -10.2565)
  point P131 (33.7547, -9.9537)
  point P132 (33.5331, -9.6585)
  point P133 (33.3307, -9.371)
  point P134 (33.1473, -9.0911)
  point P135 (32.9831, -8.8189)
  point P136 (32.838, -8.5543)
  point P137 (32.712, -8.2974)
  point P138 (32.6052, -8.0481)
  point P139 (32.5174, -7.8065)
  point P140 (32.4488, -7.5725)
  point P141 (32.3993, -7.3462)
  point P142 (32.3689, -7.1275)
  point P143 (32.3576, -6.9165)
  point P144 (32.3654, -6.7132)
extrude "Logo 1 (1)" add sketch "Logo 1" along normal mid plane 2.5
ref_plane "WorkPlane17" through (0, 0, 64.4928) normal (0, 0, 1) x (1, 0, 0)